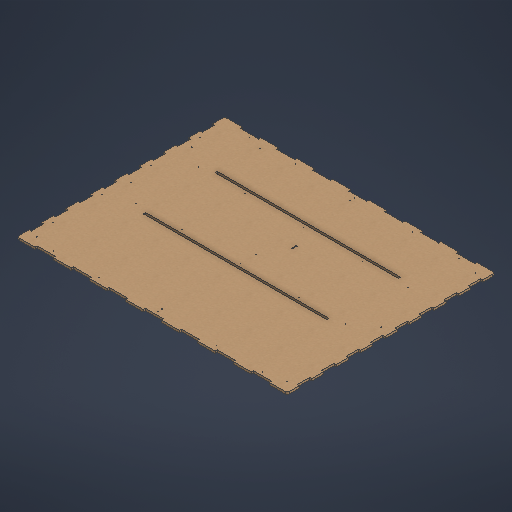
# Autodesk Inventor part: LowerBase
Saved by Autodesk Inventor 2027.1 (Build 311270010, 270A)
## iProperties
Created: 2026-10-13
Part Number: LowerBase
Material: MDF Medium Density Fiberboard
Document SubType Name: Modeling
Designer: SDS Scholar
Density: 0.8 g/cm^3
Appearance: Cardboard - Corrugated
Mass: 3329.89 g
Surface Area: 12111.4 cm^2
Volume: 4162.37 cm^3
Author: SDS Scholar
Autodesk Inventor part; units mm, degrees
ref_plane "YZ Plane" through (0, 0, 0) normal (1, 0, 0) x (0, 1, 0)
ref_plane "XZ Plane" through (0, 0, 0) normal (0, 1, 0) x (-1, 0, 0)
ref_plane "XY Plane" through (0, 0, 0) normal (0, 0, 1) x (1, 0, 0)
sketch "Sketch1" plane through (0, 0, 0) normal (0, 1, 0) x (-1, 0, 0)
  line L0 (442.5, 340) -> (-442.5, 340)
  line L1 (-442.5, 340) -> (-442.5, -340)
  line L2 (-442.5, -340) -> (442.5, -340)
  line L3 (442.5, -340) -> (442.5, 340)
  point P0 (0, 0)
  point P1 (442.5, 0)
  point P2 (0, -340)
  dimension "d0" = 680
  dimension "d1" = 885
  constraints: 8 end point, 2 midpoint, 2 parallel, 1 horizontal, 1 horizontal alignment, 1 perpendicular, 1 vertical alignment
  measures "d0" distance of L2.end L0.start
  measures "d1" distance of L0.start L0.end
extrude "Extrusion1" add sketch "Sketch1" against normal blind 7
sketch "Sketch2" plane through (0, 0, 0) normal (0, 1, 0) x (1, 0, 0)
  line L0 (442.5, -340) -> (442.5, 340) projected
  line L1 (442.5, 340) -> (-442.5, 340) projected
  line L2 (-442.5, 340) -> (-442.5, -340) projected
  line L3 (-442.5, -340) -> (442.5, -340) projected
  line L4 (-435.5, 333) -> (435.5, 333)
  line L5 (435.5, 333) -> (435.5, -333)
  line L6 (435.5, -333) -> (-435.5, -333)
  line L7 (-435.5, -333) -> (-435.5, 333)
  line L8 (0, 333) -> (0, -333) construction
  line L9 (-435.5, 0) -> (435.5, 0) construction
  line L10 (-442.5, 340) -> (-383.5, 340)
  line L11 (-383.5, 340) -> (-383.5, 333)
  line L12 (-383.5, 333) -> (-442.5, 333)
  line L13 (-442.5, 333) -> (-442.5, 340)
  line L14 (-383.5, 340) -> (-324.5, 340)
  line L15 (-324.5, 340) -> (-324.5, 333)
  line L16 (-324.5, 333) -> (-383.5, 333)
  line L17 (-383.5, 333) -> (-383.5, 340)
  line L18 (-265.5, 340) -> (-265.5, 333)
  line L19 (-206.5, 340) -> (-206.5, 333)
  line L20 (-147.5, 340) -> (-147.5, 333)
  line L21 (-88.5, 340) -> (-88.5, 333)
  line L22 (-29.5, 340) -> (-29.5, 333)
  line L23 (29.5, 340) -> (29.5, 333)
  line L24 (88.5, 340) -> (88.5, 333)
  line L25 (147.5, 340) -> (147.5, 333)
  line L26 (206.5, 340) -> (206.5, 333)
  line L27 (265.5, 340) -> (265.5, 333)
  line L28 (324.5, 340) -> (324.5, 333)
  line L29 (383.5, 340) -> (383.5, 333)
  line L30 (-383.5, -340) -> (-383.5, -333)
  line L31 (-324.5, -340) -> (-324.5, -333)
  line L32 (-265.5, -340) -> (-265.5, -333)
  line L33 (-206.5, -340) -> (-206.5, -333)
  line L34 (-147.5, -340) -> (-147.5, -333)
  line L35 (-88.5, -340) -> (-88.5, -333)
  line L36 (-29.5, -340) -> (-29.5, -333)
  line L37 (29.5, -340) -> (29.5, -333)
  line L38 (88.5, -340) -> (88.5, -333)
  line L39 (147.5, -340) -> (147.5, -333)
  line L40 (206.5, -340) -> (206.5, -333)
  line L41 (265.5, -340) -> (265.5, -333)
  line L42 (324.5, -340) -> (324.5, -333)
  line L43 (383.5, -340) -> (383.5, -333)
  line L44 (-442.5, 340) -> (-435.5, 340)
  line L45 (-435.5, 340) -> (-435.5, 300)
  line L46 (-435.5, 300) -> (-442.5, 300)
  line L47 (-442.5, 300) -> (-442.5, 340)
  line L48 (-442.5, 300) -> (-435.5, 300)
  line L49 (-435.5, 300) -> (-435.5, 260)
  line L50 (-435.5, 260) -> (-442.5, 260)
  line L51 (-442.5, 260) -> (-442.5, 300)
  line L52 (-435.5, 220) -> (-442.5, 220)
  line L53 (-435.5, 180) -> (-442.5, 180)
  line L54 (-435.5, 140) -> (-442.5, 140)
  line L55 (-435.5, 100) -> (-442.5, 100)
  line L56 (-435.5, 60) -> (-442.5, 60)
  line L57 (-435.5, 20) -> (-442.5, 20)
  line L58 (-435.5, -20) -> (-442.5, -20)
  line L59 (-435.5, -60) -> (-442.5, -60)
  line L60 (-435.5, -100) -> (-442.5, -100)
  line L61 (-435.5, -140) -> (-442.5, -140)
  line L62 (-435.5, -180) -> (-442.5, -180)
  line L63 (-435.5, -220) -> (-442.5, -220)
  line L64 (-435.5, -260) -> (-442.5, -260)
  line L65 (-435.5, -300) -> (-442.5, -300)
  line L66 (435.5, 300) -> (442.5, 300)
  line L67 (435.5, 260) -> (442.5, 260)
  line L68 (435.5, 220) -> (442.5, 220)
  line L69 (435.5, 180) -> (442.5, 180)
  line L70 (435.5, 140) -> (442.5, 140)
  line L71 (435.5, 100) -> (442.5, 100)
  line L72 (435.5, 60) -> (442.5, 60)
  line L73 (435.5, 20) -> (442.5, 20)
  line L74 (435.5, -20) -> (442.5, -20)
  line L75 (435.5, -60) -> (442.5, -60)
  line L76 (435.5, -100) -> (442.5, -100)
  line L77 (435.5, -140) -> (442.5, -140)
  line L78 (435.5, -180) -> (442.5, -180)
  line L79 (435.5, -220) -> (442.5, -220)
  line L80 (435.5, -260) -> (442.5, -260)
  line L81 (435.5, -300) -> (442.5, -300)
  point P0 (0, 0)
  point P1 (0, 0)
  point P2 (-435.5, -60)
  point P3 (-435.5, -20)
  point P4 (-435.5, -140)
  point P5 (-435.5, -100)
  point P6 (-435.5, -220)
  point P7 (-435.5, -180)
  point P8 (-435.5, -300)
  point P9 (-435.5, -260)
  point P10 (-324.5, -340)
  point P11 (-324.5, -333)
  point P12 (-383.5, -333)
  point P13 (-383.5, -340)
  point P14 (-206.5, -333)
  point P15 (-265.5, -333)
  point P16 (-88.5, -333)
  point P17 (29.5, -333)
  point P18 (147.5, -333)
  point P19 (265.5, -333)
  point P20 (383.5, -340)
  point P21 (324.5, -333)
  point P22 (324.5, -340)
  point P23 (442.5, -260)
  point P24 (435.5, -260)
  point P25 (435.5, -300)
  point P26 (442.5, -300)
  point P27 (435.5, -220)
  point P28 (442.5, -220)
  point P29 (435.5, 60)
  point P30 (435.5, 20)
  point P31 (435.5, 140)
  point P32 (435.5, 100)
  point P33 (442.5, 220)
  point P34 (435.5, 220)
  point P35 (435.5, 180)
  point P36 (442.5, 300)
  point P37 (442.5, 260)
  point P38 (324.5, 333)
  point P39 (147.5, 333)
  point P40 (29.5, 333)
  point P41 (-88.5, 333)
  point P42 (-206.5, 333)
  point P43 (-265.5, 333)
  dimension "d70" = 3
  dimension "d71" = 8.5
  dimension "d72" = 100
  dimension "d73" = 8.5
  dimension "d74" = 3
  dimension "d75" = 5.8
  dimension "d76" = 8.5
  dimension "d77" = 150
  dimension "d78" = 3
  dimension "d79" = 5.8
  dimension "d80" = 8.5
  dimension "d81" = 3
  dimension "d82" = 5.8
  dimension "d83" = 8.5
  dimension "d84" = 100
  dimension "d85" = 3
  dimension "d86" = 5.8
  dimension "d87" = 8.5
  dimension "d88" = 160
  dimension "d91" = 2
  dimension "d92" = 2
  dimension "d94" = 2
  dimension "d95" = 2
  dimension "d96" = 2
  dimension "d4" = 7
  dimension "d5" = 59
  dimension "d6" = 59
  dimension "d9" = 118
  dimension "d14" = 40
  dimension "d15" = 40
  dimension "d18" = 80
  constraints: 156 end point, 60 symmetric about line, 8 parallel, 6 midpoint, 5 horizontal, 5 perpendicular, 4 point on line, 1 coincident, 1 vertical, 81 other
  measures "d4" distance between parallel lines of L1 L4
  measures "d5" distance between parallel lines of L2 L11
  measures "d6" distance between parallel lines of L15 L11
  measures "d9" distance of L10.end L18.start
  measures "d14" distance between parallel lines of L46 L10
  measures "d15" distance between parallel lines of L46 L50
  measures "d18" distance of L45.end L52.start
extrude "Extrusion2" cut sketch "Sketch2" against normal through all contours L81 L5 L80 L0 | L3 L42 L6 L43 | L79 L5 L78 L0 | L3 L40 L6 L41 | L77 L5 L76 L0 | L3 L38 L6 L39 | L75 L5 L74 L0 | L3 L36 L6 L37 | L73 L5 L72 L0 | L3 L34 L6 L35 | L71 L5 L70 L0 | L3 L32 L6 L33 | L69 L5 L68 L0 | L3 L30 L6 L31 | L67 L5 L66 L0 | L2 L64 L7 L65 | L29 L4 L28 L1 | L2 L62 L7 L63 | L27 L4 L26 L1 | L2 L60 L7 L61 | L25 L4 L24 L1 | L2 L58 L7 L59 | L23 L4 L22 L1 | L2 L56 L7 L57 | L21 L4 L20 L1 | L2 L54 L7 L55 | L19 L4 L18 L1 | L2 L52 L7 L53 | L15 L4 L11 L1 | L2 L46 L7 L50
fillet "Fillet2" radius 7 4 edges at (442.5, -3.5, 340) (442.5, -3.5, -340) (-442.5, -3.5, -340) (-442.5, -3.5, 340)
sketch "Sketch6" plane through (0, 0, 0) normal (0, 1, 0) x (1, 0, 0)
  line L0 (-442.5, 20) -> (-442.5, -20) projected
  line L1 (442.5, -20) -> (442.5, 20) projected
  line L2 (29.5, 333) -> (-29.5, 333) projected
  line L3 (-29.5, -333) -> (29.5, -333) projected
  line L4 (-342.5, 324.5) -> (-342.5, 321.5) construction
  line L5 (-346.75, 324.5) -> (-346.75, 321.5)
  line L6 (-338.25, 321.5) -> (-338.25, 324.5)
  arc A0 (-338.25, 324.5) -> (-346.75, 324.5) centre (-342.5, 324.5) ccw
  arc A1 (-346.75, 321.5) -> (-338.25, 321.5) centre (-342.5, 321.5) ccw
  line L7 (-442.5, 333) -> (-442.5, 300) projected
  line L8 (-324.5, 333) -> (-383.5, 333) projected
  line L9 (-192.5, 324.5) -> (-192.5, 321.5) construction
  line L10 (-195.4, 324.5) -> (-195.4, 321.5)
  line L11 (-189.6, 321.5) -> (-189.6, 324.5)
  arc A2 (-189.6, 324.5) -> (-195.4, 324.5) centre (-192.5, 324.5) ccw
  arc A3 (-195.4, 321.5) -> (-189.6, 321.5) centre (-192.5, 321.5) ccw
  line L12 (-88.5, 333) -> (-147.5, 333) projected
  line L13 (0, 324.5) -> (0, 321.5) construction
  line L14 (-2.9, 324.5) -> (-2.9, 321.5)
  line L15 (2.9, 321.5) -> (2.9, 324.5)
  arc A4 (2.9, 324.5) -> (-2.9, 324.5) centre (0, 324.5) ccw
  arc A5 (-2.9, 321.5) -> (2.9, 321.5) centre (0, 321.5) ccw
  line L16 (-442.5, 0) -> (442.5, 0) construction
  line L17 (0, 333) -> (0, -333) construction
  line L18 (-427, 240) -> (-424, 240) construction
  line L19 (-427, 237.1) -> (-424, 237.1)
  line L20 (-424, 242.9) -> (-427, 242.9)
  arc A6 (-427, 242.9) -> (-427, 237.1) centre (-427, 240) ccw
  arc A7 (-424, 237.1) -> (-424, 242.9) centre (-424, 240) ccw
  line L21 (-435.5, 300) -> (-435.5, 260) projected
  line L22 (-383.5, 340) -> (-435.5, 340) projected
  line L23 (-427, 80) -> (-424, 80) construction
  line L24 (-427, 77.1) -> (-424, 77.1)
  line L25 (-424, 82.9) -> (-427, 82.9)
  arc A8 (-427, 82.9) -> (-427, 77.1) centre (-427, 80) ccw
  arc A9 (-424, 77.1) -> (-424, 82.9) centre (-424, 80) ccw
  line L26 (-435.5, 220) -> (-435.5, 180) projected
  circle A10 centre (-192.5, 321.5) radius 1
  circle A11 centre (-342.5, 321.5) radius 1
  circle A12 centre (0, 321.5) radius 1
  circle A13 centre (-424, 240) radius 1
  circle A14 centre (-424, 80) radius 1
  circle A15 centre (192.5, 321.5) radius 1
  circle A16 centre (342.5, 321.5) radius 1
  circle A17 centre (424, 240) radius 1
  circle A18 centre (424, 80) radius 1
  circle A19 centre (-192.5, -321.5) radius 1
  circle A20 centre (-342.5, -321.5) radius 1
  circle A21 centre (0, -321.5) radius 1
  circle A22 centre (-424, -240) radius 1
  circle A23 centre (-424, -80) radius 1
  circle A24 centre (342.5, -321.5) radius 1
  circle A25 centre (192.5, -321.5) radius 1
  circle A26 centre (424, -240) radius 1
  circle A27 centre (424, -80) radius 1
  point P0 (0, 0)
  point P1 (-342.5, 323)
  point P2 (-192.5, 323)
  point P3 (0, 323)
  point P4 (-425.5, 240)
  point P5 (-425.5, 80)
  dimension "d70" = 3
  dimension "d71" = 8.5
  dimension "d72" = 100
  dimension "d73" = 8.5
  dimension "d74" = 3
  dimension "d75" = 5.8
  dimension "d76" = 8.5
  dimension "d77" = 150
  dimension "d78" = 3
  dimension "d79" = 5.8
  dimension "d80" = 8.5
  dimension "d81" = 3
  dimension "d82" = 5.8
  dimension "d83" = 8.5
  dimension "d84" = 100
  dimension "d85" = 3
  dimension "d86" = 5.8
  dimension "d87" = 8.5
  dimension "d88" = 160
  dimension "d91" = 2
  dimension "d92" = 2
  dimension "d94" = 2
  dimension "d95" = 2
  dimension "d96" = 2
  constraints: 44 end point, 28 centre point, 20 point on circle, 20 tangent, 13 symmetric about line, 9 midpoint, 5 parallel, 4 coincident, 3 vertical, 2 horizontal, 2 vertical alignment, 1 horizontal alignment, 13 other
  measures "d70" distance of L4.start L4.end
  measures "d71" diameter of A1
  measures "d72" distance between parallel lines of L7 L4
  measures "d73" distance from line of L8 L4.start
  measures "d74" distance of L9.start L9.end
  measures "d75" diameter of A3
  measures "d76" distance from line of L12 L9.start
  measures "d77" distance between parallel lines of L4 L9
  measures "d78" distance of L13.start L13.end
  measures "d79" diameter of A5
  measures "d80" distance from line of L2 L13.start
  measures "d81" distance of L18.start L18.end
  measures "d82" diameter of A7
  measures "d83" distance from line of L21 L18.start
  measures "d84" distance between parallel lines of L22 L18
  measures "d85" distance of L23.start L23.end
  measures "d86" diameter of A9
  measures "d87" distance from line of L26 L23.start
  measures "d88" distance between parallel lines of L23 L18
  measures "d91" diameter of A10
  measures "d92" diameter of A11
  measures "d94" diameter of A12
  measures "d95" diameter of A13
  measures "d96" diameter of A14
extrude "Extrusion5" cut sketch "Sketch6" against normal through all contours A10 | A11 | A12 | A13 | A14 | A15 | A16 | A19 | A20 | A21 | A22 | A23 | A24 | A25
sketch "Sketch7" plane through (0, 0, 0) normal (0, 1, 0) x (1, 0, 0)
  circle A0 centre (-424, 80) radius 1 projected
  circle A1 centre (-192.5, -321.5) radius 1 projected
  circle A2 centre (192.5, -321.5) radius 1 projected
  circle A3 centre (342.5, 321.5) radius 1 projected
  circle A4 centre (-192.5, 321.5) radius 1 projected
  circle A5 centre (-342.5, -321.5) radius 1 projected
  circle A6 centre (-424, 240) radius 1 projected
  circle A7 centre (-424, -80) radius 1 projected
  circle A8 centre (0, -321.5) radius 1 projected
  circle A9 centre (192.5, 321.5) radius 1 projected
  circle A10 centre (0, 321.5) radius 1 projected
  circle A11 centre (342.5, -321.5) radius 1 projected
  circle A12 centre (-424, -240) radius 1 projected
  circle A13 centre (-342.5, 321.5) radius 1 projected
  arc A14 (-442.5, -333) -> (-435.5, -340) centre (-435.5, -333) ccw projected
  line L0 (-435.5, -340) -> (-383.5, -340) projected
  line L1 (-383.5, -340) -> (-383.5, -333) projected
  line L2 (-383.5, -333) -> (-324.5, -333) projected
  line L3 (-324.5, -333) -> (-324.5, -340) projected
  line L4 (-324.5, -340) -> (-265.5, -340) projected
  line L5 (-265.5, -340) -> (-265.5, -333) projected
  line L6 (-265.5, -333) -> (-206.5, -333) projected
  line L7 (-206.5, -333) -> (-206.5, -340) projected
  line L8 (-206.5, -340) -> (-147.5, -340) projected
  line L9 (-147.5, -340) -> (-147.5, -333) projected
  line L10 (-147.5, -333) -> (-88.5, -333) projected
  line L11 (-88.5, -333) -> (-88.5, -340) projected
  line L12 (-88.5, -340) -> (-29.5, -340) projected
  line L13 (-29.5, -340) -> (-29.5, -333) projected
  line L14 (-29.5, -333) -> (29.5, -333) projected
  line L15 (29.5, -333) -> (29.5, -340) projected
  line L16 (29.5, -340) -> (88.5, -340) projected
  line L17 (88.5, -340) -> (88.5, -333) projected
  line L18 (88.5, -333) -> (147.5, -333) projected
  line L19 (147.5, -333) -> (147.5, -340) projected
  line L20 (147.5, -340) -> (206.5, -340) projected
  line L21 (206.5, -340) -> (206.5, -333) projected
  line L22 (206.5, -333) -> (265.5, -333) projected
  line L23 (265.5, -333) -> (265.5, -340) projected
  line L24 (265.5, -340) -> (324.5, -340) projected
  line L25 (324.5, -340) -> (324.5, -333) projected
  line L26 (324.5, -333) -> (383.5, -333) projected
  line L27 (383.5, -333) -> (383.5, -340) projected
  line L28 (383.5, -340) -> (435.5, -340) projected
  arc A15 (435.5, -340) -> (442.5, -333) centre (435.5, -333) ccw projected
  line L29 (442.5, -333) -> (442.5, -300) projected
  line L30 (442.5, -300) -> (435.5, -300) projected
  line L31 (435.5, -300) -> (435.5, -260) projected
  line L32 (435.5, -260) -> (442.5, -260) projected
  line L33 (442.5, -260) -> (442.5, -220) projected
  line L34 (442.5, -220) -> (435.5, -220) projected
  line L35 (435.5, -220) -> (435.5, -180) projected
  line L36 (435.5, -180) -> (442.5, -180) projected
  line L37 (442.5, -180) -> (442.5, -140) projected
  line L38 (442.5, -140) -> (435.5, -140) projected
  line L39 (435.5, -140) -> (435.5, -100) projected
  line L40 (435.5, -100) -> (442.5, -100) projected
  line L41 (442.5, -100) -> (442.5, -60) projected
  line L42 (442.5, -60) -> (435.5, -60) projected
  line L43 (435.5, -60) -> (435.5, -20) projected
  line L44 (435.5, -20) -> (442.5, -20) projected
  line L45 (442.5, -20) -> (442.5, 20) projected
  line L46 (442.5, 20) -> (435.5, 20) projected
  line L47 (435.5, 20) -> (435.5, 60) projected
  line L48 (435.5, 60) -> (442.5, 60) projected
  line L49 (442.5, 60) -> (442.5, 100) projected
  line L50 (442.5, 100) -> (435.5, 100) projected
  line L51 (435.5, 100) -> (435.5, 140) projected
  line L52 (435.5, 140) -> (442.5, 140) projected
  line L53 (442.5, 140) -> (442.5, 180) projected
  line L54 (442.5, 180) -> (435.5, 180) projected
  line L55 (435.5, 180) -> (435.5, 220) projected
  line L56 (435.5, 220) -> (442.5, 220) projected
  line L57 (442.5, 220) -> (442.5, 260) projected
  line L58 (442.5, 260) -> (435.5, 260) projected
  line L59 (435.5, 260) -> (435.5, 300) projected
  line L60 (435.5, 300) -> (442.5, 300) projected
  line L61 (442.5, 300) -> (442.5, 333) projected
  arc A16 (442.5, 333) -> (435.5, 340) centre (435.5, 333) ccw projected
  line L62 (435.5, 340) -> (383.5, 340) projected
  line L63 (383.5, 340) -> (383.5, 333) projected
  line L64 (383.5, 333) -> (324.5, 333) projected
  line L65 (324.5, 333) -> (324.5, 340) projected
  line L66 (324.5, 340) -> (265.5, 340) projected
  line L67 (265.5, 340) -> (265.5, 333) projected
  line L68 (265.5, 333) -> (206.5, 333) projected
  line L69 (206.5, 333) -> (206.5, 340) projected
  line L70 (206.5, 340) -> (147.5, 340) projected
  line L71 (147.5, 340) -> (147.5, 333) projected
  line L72 (147.5, 333) -> (88.5, 333) projected
  line L73 (88.5, 333) -> (88.5, 340) projected
  line L74 (88.5, 340) -> (29.5, 340) projected
  line L75 (29.5, 340) -> (29.5, 333) projected
  line L76 (29.5, 333) -> (-29.5, 333) projected
  line L77 (-29.5, 333) -> (-29.5, 340) projected
  line L78 (-29.5, 340) -> (-88.5, 340) projected
  line L79 (-88.5, 340) -> (-88.5, 333) projected
  line L80 (-88.5, 333) -> (-147.5, 333) projected
  line L81 (-147.5, 333) -> (-147.5, 340) projected
  line L82 (-147.5, 340) -> (-206.5, 340) projected
  line L83 (-206.5, 340) -> (-206.5, 333) projected
  line L84 (-206.5, 333) -> (-265.5, 333) projected
  line L85 (-265.5, 333) -> (-265.5, 340) projected
  line L86 (-265.5, 340) -> (-324.5, 340) projected
  line L87 (-324.5, 340) -> (-324.5, 333) projected
  line L88 (-324.5, 333) -> (-383.5, 333) projected
  line L89 (-383.5, 333) -> (-383.5, 340) projected
  line L90 (-383.5, 340) -> (-435.5, 340) projected
  arc A17 (-435.5, 340) -> (-442.5, 333) centre (-435.5, 333) ccw projected
  line L91 (-442.5, 333) -> (-442.5, 300) projected
  line L92 (-442.5, 300) -> (-435.5, 300) projected
  line L93 (-435.5, 300) -> (-435.5, 260) projected
  line L94 (-435.5, 260) -> (-442.5, 260) projected
  line L95 (-442.5, 260) -> (-442.5, 220) projected
  line L96 (-442.5, 220) -> (-435.5, 220) projected
  line L97 (-435.5, 220) -> (-435.5, 180) projected
  line L98 (-435.5, 180) -> (-442.5, 180) projected
  line L99 (-442.5, 180) -> (-442.5, 140) projected
  line L100 (-442.5, 140) -> (-435.5, 140) projected
  line L101 (-435.5, 140) -> (-435.5, 100) projected
  line L102 (-435.5, 100) -> (-442.5, 100) projected
  line L103 (-442.5, 100) -> (-442.5, 60) projected
  line L104 (-442.5, 60) -> (-435.5, 60) projected
  line L105 (-435.5, 60) -> (-435.5, 20) projected
  line L106 (-435.5, 20) -> (-442.5, 20) projected
  line L107 (-442.5, 20) -> (-442.5, -20) projected
  line L108 (-442.5, -20) -> (-435.5, -20) projected
  line L109 (-435.5, -20) -> (-435.5, -60) projected
  line L110 (-435.5, -60) -> (-442.5, -60) projected
  line L111 (-442.5, -60) -> (-442.5, -100) projected
  line L112 (-442.5, -100) -> (-435.5, -100) projected
  line L113 (-435.5, -100) -> (-435.5, -140) projected
  line L114 (-435.5, -140) -> (-442.5, -140) projected
  line L115 (-442.5, -140) -> (-442.5, -180) projected
  line L116 (-442.5, -180) -> (-435.5, -180) projected
  line L117 (-435.5, -180) -> (-435.5, -220) projected
  line L118 (-435.5, -220) -> (-442.5, -220) projected
  line L119 (-442.5, -220) -> (-442.5, -260) projected
  line L120 (-442.5, -260) -> (-435.5, -260) projected
  line L121 (-435.5, -260) -> (-435.5, -300) projected
  line L122 (-435.5, -300) -> (-442.5, -300) projected
  line L123 (-442.5, -300) -> (-442.5, -333) projected
  line L124 (-300, 173) -> (300, 173)
  line L125 (300, 173) -> (300, 166)
  line L126 (300, 166) -> (-300, 166)
  line L127 (-300, 166) -> (-300, 173)
  line L128 (-300, -61) -> (300, -61)
  line L129 (300, -61) -> (300, -68)
  line L130 (300, -68) -> (-300, -68)
  line L131 (-300, -68) -> (-300, -61)
  circle A18 centre (-342.5, 321.5) radius 1
  circle A19 centre (-192.5, 321.5) radius 1
  circle A20 centre (0, 321.5) radius 1
  circle A21 centre (192.5, 321.5) radius 1
  circle A22 centre (342.5, 321.5) radius 1
  circle A23 centre (-342.5, 155.5) radius 1
  circle A24 centre (-192.5, 155.5) radius 1
  circle A25 centre (192.5, 155.5) radius 1
  circle A26 centre (342.5, 155.5) radius 1
  circle A27 centre (-342.5, -321.5) radius 1
  circle A28 centre (-192.5, -321.5) radius 1
  circle A29 centre (0, -321.5) radius 1
  circle A30 centre (192.5, -321.5) radius 1
  circle A31 centre (342.5, -321.5) radius 1
  circle A32 centre (-342.5, -50.5) radius 1
  circle A33 centre (-192.5, -50.5) radius 1
  circle A34 centre (0, -50.5) radius 1
  circle A35 centre (192.5, -50.5) radius 1
  circle A36 centre (342.5, -50.5) radius 1
  circle A37 centre (0, 155.5) radius 1
  point P0 (0, 0)
  point P1 (0, 166)
  point P2 (0, -68)
  dimension "d99" = 600
  dimension "d100" = 7
  dimension "d101" = 160
  dimension "d102" = 600
  dimension "d103" = 7
  dimension "d104" = 265
  dimension "d107" = 166
  dimension "d117" = 271
  dimension "d125" = 2
  constraints: 20 centre point, 16 end point, 12 coincident, 10 concentric, 4 parallel, 2 horizontal, 2 midpoint, 2 perpendicular, 2 vertical, 2 vertical alignment, 20 other
  measures "d99" distance of L125.end L126.end
  measures "d100" distance of L124.end L125.end
  measures "d101" distance between parallel lines of L76 L124
  measures "d102" distance of L129.end L130.end
  measures "d103" distance of L128.end L129.end
  measures "d104" distance between parallel lines of L14 L130
  measures "d107" distance of A13.centre point (-342.5, 155.5)
  measures "d117" distance of A27.centre A32.centre
  measures "d125" diameter of A37
extrude "Extrusion6" cut sketch "Sketch7" against normal through all contours L124 L125 L126 L127 | L128 L129 L130 L131 | A23 | A24 | A25 | A26 | A32 | A33 | A34 | A35 | A36 | A37
sketch "Sketch8" plane through (0, 0, 0) normal (0, 1, 0) x (1, 0, 0)
  line L0 (44.5, 75) -> (44.5, 95) projected
  line L1 (39.5, 77.5) -> (39.5, 92.5) projected
  line L2 (42.5, 92.5) -> (42.5, 77.5) projected
  line L3 (39.5, 92.5) -> (42.5, 92.5) projected
  line L4 (42.5, 77.5) -> (39.5, 77.5) projected
  point P0 (0, 0)
extrude "Extrusion7" cut sketch "Sketch8" against normal through all
sketch "Sketch9" plane through (0, 0, 0) normal (0, 1, 0) x (1, 0, 0)
  line L0 (39.5, 92.5) -> (42.5, 92.5) projected
  line L1 (42.5, 92.5) -> (42.5, 77.5) projected
  line L2 (42.5, 77.5) -> (39.5, 77.5) projected
  line L3 (39.5, 77.5) -> (39.5, 92.5) projected
  circle A0 centre (0, 155.5) radius 1 projected
  circle A1 centre (-342.5, -50.5) radius 1 projected
  circle A2 centre (192.5, -50.5) radius 1 projected
  circle A3 centre (0, -50.5) radius 1 projected
  circle A4 centre (-342.5, 155.5) radius 1 projected
  line L4 (300, 173) -> (300, 166) projected
  line L5 (300, 166) -> (-300, 166) projected
  line L6 (-300, 166) -> (-300, 173) projected
  line L7 (-300, 173) -> (300, 173) projected
  circle A5 centre (342.5, 155.5) radius 1 projected
  line L8 (300, -61) -> (300, -68) projected
  line L9 (300, -68) -> (-300, -68) projected
  line L10 (-300, -68) -> (-300, -61) projected
  line L11 (-300, -61) -> (300, -61) projected
  circle A6 centre (342.5, -50.5) radius 1 projected
  circle A7 centre (-192.5, -50.5) radius 1 projected
  circle A8 centre (192.5, 155.5) radius 1 projected
  circle A9 centre (-192.5, 155.5) radius 1 projected
  circle A10 centre (-424, 80) radius 1 projected
  circle A11 centre (-192.5, -321.5) radius 1 projected
  circle A12 centre (342.5, 321.5) radius 1 projected
  circle A13 centre (-192.5, 321.5) radius 1 projected
  circle A14 centre (192.5, -321.5) radius 1 projected
  circle A15 centre (-342.5, -321.5) radius 1 projected
  circle A16 centre (-424, 240) radius 1 projected
  circle A17 centre (-424, -80) radius 1 projected
  circle A18 centre (0, -321.5) radius 1 projected
  circle A19 centre (192.5, 321.5) radius 1 projected
  circle A20 centre (0, 321.5) radius 1 projected
  circle A21 centre (342.5, -321.5) radius 1 projected
  circle A22 centre (-424, -240) radius 1 projected
  circle A23 centre (-342.5, 321.5) radius 1 projected
  arc A24 (-442.5, -333) -> (-435.5, -340) centre (-435.5, -333) ccw projected
  line L12 (-435.5, -340) -> (-383.5, -340) projected
  line L13 (-383.5, -340) -> (-383.5, -333) projected
  line L14 (-383.5, -333) -> (-324.5, -333) projected
  line L15 (-324.5, -333) -> (-324.5, -340) projected
  line L16 (-324.5, -340) -> (-265.5, -340) projected
  line L17 (-265.5, -340) -> (-265.5, -333) projected
  line L18 (-265.5, -333) -> (-206.5, -333) projected
  line L19 (-206.5, -333) -> (-206.5, -340) projected
  line L20 (-206.5, -340) -> (-147.5, -340) projected
  line L21 (-147.5, -340) -> (-147.5, -333) projected
  line L22 (-147.5, -333) -> (-88.5, -333) projected
  line L23 (-88.5, -333) -> (-88.5, -340) projected
  line L24 (-88.5, -340) -> (-29.5, -340) projected
  line L25 (-29.5, -340) -> (-29.5, -333) projected
  line L26 (-29.5, -333) -> (29.5, -333) projected
  line L27 (29.5, -333) -> (29.5, -340) projected
  line L28 (29.5, -340) -> (88.5, -340) projected
  line L29 (88.5, -340) -> (88.5, -333) projected
  line L30 (88.5, -333) -> (147.5, -333) projected
  line L31 (147.5, -333) -> (147.5, -340) projected
  line L32 (147.5, -340) -> (206.5, -340) projected
  line L33 (206.5, -340) -> (206.5, -333) projected
  line L34 (206.5, -333) -> (265.5, -333) projected
  line L35 (265.5, -333) -> (265.5, -340) projected
  line L36 (265.5, -340) -> (324.5, -340) projected
  line L37 (324.5, -340) -> (324.5, -333) projected
  line L38 (324.5, -333) -> (383.5, -333) projected
  line L39 (383.5, -333) -> (383.5, -340) projected
  line L40 (383.5, -340) -> (435.5, -340) projected
  arc A25 (435.5, -340) -> (442.5, -333) centre (435.5, -333) ccw projected
  line L41 (442.5, -333) -> (442.5, -300) projected
  line L42 (442.5, -300) -> (435.5, -300) projected
  line L43 (435.5, -300) -> (435.5, -260) projected
  line L44 (435.5, -260) -> (442.5, -260) projected
  line L45 (442.5, -260) -> (442.5, -220) projected
  line L46 (442.5, -220) -> (435.5, -220) projected
  line L47 (435.5, -220) -> (435.5, -180) projected
  line L48 (435.5, -180) -> (442.5, -180) projected
  line L49 (442.5, -180) -> (442.5, -140) projected
  line L50 (442.5, -140) -> (435.5, -140) projected
  line L51 (435.5, -140) -> (435.5, -100) projected
  line L52 (435.5, -100) -> (442.5, -100) projected
  line L53 (442.5, -100) -> (442.5, -60) projected
  line L54 (442.5, -60) -> (435.5, -60) projected
  line L55 (435.5, -60) -> (435.5, -20) projected
  line L56 (435.5, -20) -> (442.5, -20) projected
  line L57 (442.5, -20) -> (442.5, 20) projected
  line L58 (442.5, 20) -> (435.5, 20) projected
  line L59 (435.5, 20) -> (435.5, 60) projected
  line L60 (435.5, 60) -> (442.5, 60) projected
  line L61 (442.5, 60) -> (442.5, 100) projected
  line L62 (442.5, 100) -> (435.5, 100) projected
  line L63 (435.5, 100) -> (435.5, 140) projected
  line L64 (435.5, 140) -> (442.5, 140) projected
  line L65 (442.5, 140) -> (442.5, 180) projected
  line L66 (442.5, 180) -> (435.5, 180) projected
  line L67 (435.5, 180) -> (435.5, 220) projected
  line L68 (435.5, 220) -> (442.5, 220) projected
  line L69 (442.5, 220) -> (442.5, 260) projected
  line L70 (442.5, 260) -> (435.5, 260) projected
  line L71 (435.5, 260) -> (435.5, 300) projected
  line L72 (435.5, 300) -> (442.5, 300) projected
  line L73 (442.5, 300) -> (442.5, 333) projected
  arc A26 (442.5, 333) -> (435.5, 340) centre (435.5, 333) ccw projected
  line L74 (435.5, 340) -> (383.5, 340) projected
  line L75 (383.5, 340) -> (383.5, 333) projected
  line L76 (383.5, 333) -> (324.5, 333) projected
  line L77 (324.5, 333) -> (324.5, 340) projected
  line L78 (324.5, 340) -> (265.5, 340) projected
  line L79 (265.5, 340) -> (265.5, 333) projected
  line L80 (265.5, 333) -> (206.5, 333) projected
  line L81 (206.5, 333) -> (206.5, 340) projected
  line L82 (206.5, 340) -> (147.5, 340) projected
  line L83 (147.5, 340) -> (147.5, 333) projected
  line L84 (147.5, 333) -> (88.5, 333) projected
  line L85 (88.5, 333) -> (88.5, 340) projected
  line L86 (88.5, 340) -> (29.5, 340) projected
  line L87 (29.5, 340) -> (29.5, 333) projected
  line L88 (29.5, 333) -> (-29.5, 333) projected
  line L89 (-29.5, 333) -> (-29.5, 340) projected
  line L90 (-29.5, 340) -> (-88.5, 340) projected
  line L91 (-88.5, 340) -> (-88.5, 333) projected
  line L92 (-88.5, 333) -> (-147.5, 333) projected
  line L93 (-147.5, 333) -> (-147.5, 340) projected
  line L94 (-147.5, 340) -> (-206.5, 340) projected
  line L95 (-206.5, 340) -> (-206.5, 333) projected
  line L96 (-206.5, 333) -> (-265.5, 333) projected
  line L97 (-265.5, 333) -> (-265.5, 340) projected
  line L98 (-265.5, 340) -> (-324.5, 340) projected
  line L99 (-324.5, 340) -> (-324.5, 333) projected
  line L100 (-324.5, 333) -> (-383.5, 333) projected
  line L101 (-383.5, 333) -> (-383.5, 340) projected
  line L102 (-383.5, 340) -> (-435.5, 340) projected
  arc A27 (-435.5, 340) -> (-442.5, 333) centre (-435.5, 333) ccw projected
  line L103 (-442.5, 333) -> (-442.5, 300) projected
  line L104 (-442.5, 300) -> (-435.5, 300) projected
  line L105 (-435.5, 300) -> (-435.5, 260) projected
  line L106 (-435.5, 260) -> (-442.5, 260) projected
  line L107 (-442.5, 260) -> (-442.5, 220) projected
  line L108 (-442.5, 220) -> (-435.5, 220) projected
  line L109 (-435.5, 220) -> (-435.5, 180) projected
  line L110 (-435.5, 180) -> (-442.5, 180) projected
  line L111 (-442.5, 180) -> (-442.5, 140) projected
  line L112 (-442.5, 140) -> (-435.5, 140) projected
  line L113 (-435.5, 140) -> (-435.5, 100) projected
  line L114 (-435.5, 100) -> (-442.5, 100) projected
  line L115 (-442.5, 100) -> (-442.5, 60) projected
  line L116 (-442.5, 60) -> (-435.5, 60) projected
  line L117 (-435.5, 60) -> (-435.5, 20) projected
  line L118 (-435.5, 20) -> (-442.5, 20) projected
  line L119 (-442.5, 20) -> (-442.5, -20) projected
  line L120 (-442.5, -20) -> (-435.5, -20) projected
  line L121 (-435.5, -20) -> (-435.5, -60) projected
  line L122 (-435.5, -60) -> (-442.5, -60) projected
  line L123 (-442.5, -60) -> (-442.5, -100) projected
  line L124 (-442.5, -100) -> (-435.5, -100) projected
  line L125 (-435.5, -100) -> (-435.5, -140) projected
  line L126 (-435.5, -140) -> (-442.5, -140) projected
  line L127 (-442.5, -140) -> (-442.5, -180) projected
  line L128 (-442.5, -180) -> (-435.5, -180) projected
  line L129 (-435.5, -180) -> (-435.5, -220) projected
  line L130 (-435.5, -220) -> (-442.5, -220) projected
  line L131 (-442.5, -220) -> (-442.5, -260) projected
  line L132 (-442.5, -260) -> (-435.5, -260) projected
  line L133 (-435.5, -260) -> (-435.5, -300) projected
  line L134 (-435.5, -300) -> (-442.5, -300) projected
  line L135 (-442.5, -300) -> (-442.5, -333) projected
  circle A28 centre (-410.5, -308) radius 1.5
  circle A29 centre (0, -308) radius 1.5
  circle A30 centre (410.5, -308) radius 1.5
  circle A31 centre (-410.5, 0) radius 1.5
  circle A32 centre (0, 0) radius 1.5
  circle A33 centre (410.5, 0) radius 1.5
  circle A34 centre (410.5, 308) radius 1.5
  circle A35 centre (0, 308) radius 1.5
  circle A36 centre (-295, 308) radius 1.5
  circle A37 centre (-410.5, 200) radius 1.5
  point P0 (0, -333)
  point P1 (-442.5, 0)
  point P2 (442.5, 0)
  point P3 (0, 333)
  point P4 (-435.5, 200)
  point P5 (-295, 340)
  dimension "d136" = 3
  dimension "d137" = 3
  dimension "d138" = 3
  dimension "d139" = 25
  dimension "d140" = 25
  dimension "d141" = 25
  dimension "d142" = 25
  dimension "d143" = 25
  dimension "d144" = 3
  dimension "d145" = 3
  dimension "d146" = 3
  dimension "d147" = 25
  dimension "d148" = 25
  dimension "d149" = 3
  dimension "d150" = 25
  dimension "d151" = 25
  dimension "d152" = 3
  dimension "d153" = 25
  dimension "d154" = 3
  dimension "d155" = 3
  dimension "d156" = 25
  dimension "d157" = 25
  constraints: 10 centre point, 6 midpoint, 3 horizontal alignment, 3 vertical alignment, 1 coincident
  measures "d136" diameter of A28
  measures "d137" diameter of A29
  measures "d138" diameter of A30
  measures "d139" distance from line of L43 A30.centre
  measures "d140" distance from line of L38 A30.centre
  measures "d141" distance from line of L26 A29.centre
  measures "d142" distance from line of L133 A28.centre
  measures "d143" distance from line of L14 A28.centre
  measures "d144" diameter of A31
  measures "d145" diameter of A32
  measures "d146" diameter of A33
  measures "d147" distance from line of L117 A31.centre
  measures "d148" distance from line of L59 A33.centre
  measures "d149" diameter of A34
  measures "d150" distance from line of L76 A34.centre
  measures "d151" distance from line of L71 A34.centre
  measures "d152" diameter of A35
  measures "d153" distance from line of L88 A35.centre
  measures "d154" diameter of A36
  measures "d155" diameter of A37
  measures "d156" distance from line of L96 A36.centre
  measures "d157" distance from line of L109 A37.centre
extrude "Extrusion8" cut sketch "Sketch9" against normal through all contours A28 | A29 | A30 | A31 | A32 | A33 | A34 | A35 | A36 | A37
equation "\"d0\" = BaseTotalWidth"
equation "\"d1\" = BaseTotalLength"
equation "\"d2\" = BaseWoodThickness"
equation "\"d4\" = BaseWoodThickness"
equation "\"GridProcutClearance\" = 5"
equation "\"GridBorderThickness\" = 5"
equation "\"GridBorderFillets\" = 7"
equation "\"GridTotalSize\" = 65"
equation "\"GridRobotClearance\" = 65"
equation "\"AluminiumExtrusionClearance\" = 35"
equation "\"BaseTotalWidth\" = 680"
equation "\"BaseTotalLength\" = 885"
equation "\"WorkspaceLength\" = 515"
equation "\"WorkspaceHeight\" = 183"
equation "\"AxesBaseFillet\" = 15"
equation "\"Zaxis\" = 197"
equation "\"ProductTotalHeight\" = 45"
equation "\"VerticalStroke\" = 105"
equation "\"BackArea\" = 165"
equation "\"CylinderStroke\" = 75"
equation "\"BoxesWidth\" = 125"
equation "\"BaseWoodThickness\" = 7"
equation "\"kerf\" = 1.5"
equation "\"Kerf\" = 0.3"
equation "\"RxThickness\" = 1.8"
equation "\"support_2\" = 265"
body "Solid1"
